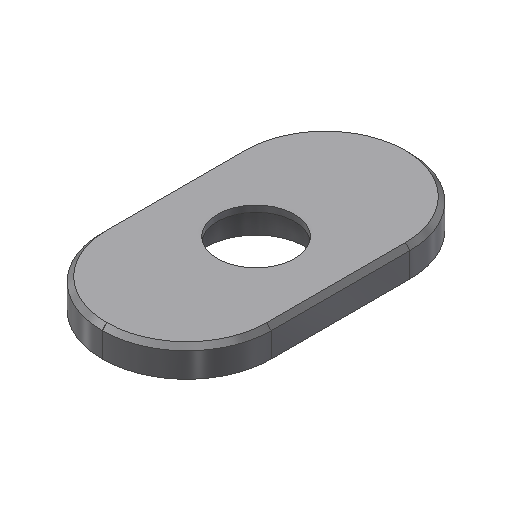
# Autodesk Inventor part: PRT - 9035 - CAMTARNDF - V04
Saved by Autodesk Inventor 2025.5 (Build 295498000, 498)
## iProperties
Created: 2026-11-05
Part Number: PRT - 9035 - CAMTARNDF - V04
Material: Generisch
Description: ND cap for the bare chip: filter D12.7 tilted by a pad, same seat and magnets. Print on the front.
Document SubType Name: Modeling
Designer: benir
Density: 1 g/cm^3
Appearance: Smooth - Light Gray
Author: benir
Autodesk Inventor part; units mm, degrees
ref_plane "y=cap_back_y" through (0, 12.3, 0) normal (0, 1, 0) x (-1, 0, 0)
sketch "cap sketch" plane through (0, 12.3, 0) normal (0, 1, 0) x (-1, 0, 0)
  line L0 (11, -20) -> (-11, -20)
  line L1 (-11, -20) -> (-11, 20)
  line L2 (-11, 20) -> (11, 20)
  line L3 (11, 20) -> (11, -20)
  line L4 (0, -28) -> (0, 28) projected
  line L5 (15.4, 0) -> (-15.4, 0) projected
  dimension "d3" = 22
  dimension "d4" = 40
  constraints: 8 end point, 2 parallel, 1 horizontal, 1 perpendicular, 2 other
  measures "d3" distance of L0.start L0.end
  measures "d4" distance of L2.end L0.start
extrude "cap" add sketch "cap sketch" along normal blind 3.8
fillet "round ends" radius 10.98 4 edges at (11, 14.2, -20) (11, 14.2, 20) (-11, 14.2, 20) (-11, 14.2, -20)
sketch "ring sketch" plane through (0, 12.3, 0) normal (0, 1, 0) x (-1, 0, 0)
  circle A0 centre (0, 0) radius 10.6
  dimension "d8" = 21.2
  constraints: 1 centre point
  measures "d8" diameter of A0
extrude "centring ring" add sketch "ring sketch" against normal blind 0.6 draft -45
ref_plane "y=ring_tip_y - 1 mm" through (0, 10.7, 0) normal (0, 1, 0) x (-1, 0, 0)
sketch "filter pocket sketch" plane through (0, 10.7, 0) normal (0, 1, 0) x (-1, 0, 0)
  circle A0 centre (0, 0) radius 6.45
  dimension "d12" = 12.9
  constraints: 1 centre point
  measures "d12" diameter of A0
extrude "filter pocket" cut sketch "filter pocket sketch" along normal blind 4.6
ref_plane "y=screen_out_y + 1 mm" through (0, 17.1, 0) normal (0, 1, 0) x (-1, 0, 0)
sketch "window sketch" plane through (0, 17.1, 0) normal (0, 1, 0) x (-1, 0, 0)
  circle A0 centre (0, 0) radius 5
  dimension "d16" = 10
  constraints: 1 centre point
  measures "d16" diameter of A0
extrude "window" cut sketch "window sketch" against normal blind 2.8
sketch "cap magnet sketch" plane through (0, 12.3, 0) normal (0, 1, 0) x (-1, 0, 0)
  circle A0 centre (0, 15.5) radius 4.1
  line L0 (0, -28) -> (0, 28) projected
  circle A1 centre (0, -15.5) radius 4.1
  point P0 (0, 0)
  dimension "d19" = 15.5
  dimension "d20" = 8.2
  dimension "d21" = 15.5
  dimension "d22" = 8.2
  constraints: 2 centre point, 2 point on line
  measures "d19" distance of point (0, 0) A0.centre
  measures "d20" diameter of A0
  measures "d21" distance of point (0, 0) A1.centre
  measures "d22" diameter of A1
extrude "magnet pockets" cut sketch "cap magnet sketch" along normal blind 3.4
chamfer "front edge" distance 0.6 angle 45 8 edges at (-7.784, 16.1, -16.784) (0, 16.1, -20) (-11, 16.1, 0) (-7.784, 16.1, 16.784) (0, 16.1, 20) (7.784, 16.1, 16.784) (11, 16.1, 0) (7.784, 16.1, -16.784)
ref_plane "y=screen_out_y - nd_wall" through (0, 15.3, 0) normal (0, 1, 0) x (-1, 0, 0)
sketch "pad sketch" plane through (0, 15.3, 0) normal (0, 1, 0) x (-1, 0, 0)
  line L0 (-5.2, -3) -> (-7.35, -3)
  line L1 (-7.35, -3) -> (-7.35, 3)
  line L2 (-7.35, 3) -> (-5.2, 3)
  line L3 (-5.2, 3) -> (-5.2, -3)
  line L4 (15.4, 0) -> (-15.4, 0) projected
  point P0 (0, 0)
  dimension "d29" = 6
  dimension "d30" = 5.2
  dimension "d31" = 7.35
  constraints: 8 end point, 2 parallel, 1 horizontal, 1 perpendicular, 1 other
  measures "d29" distance of L2.end L0.start
  measures "d30" horizontal distance of point (0, 0) L2.end
  measures "d31" horizontal distance of point (0, 0) L0.end
extrude "pad: tilts the filter" add sketch "pad sketch" against normal blind 0.7
equation "\"d3\" = 2 * cap_w"
equation "\"d4\" = 2 * cap_h"
equation "\"d5\" = cap_t"
equation "\"d8\" = ring_d0"
equation "\"d9\" = ring_h"
equation "\"d10\" = -cone_ang"
equation "\"d12\" = nd_d + nd_clr"
equation "\"d16\" = nd_win_d"
equation "\"d19\" = mag_z"
equation "\"d20\" = mag_pocket_d"
equation "\"d21\" = mag_z"
equation "\"d22\" = mag_pocket_d"
equation "\"d23\" = mag_pocket_h"
equation "\"d25\" = cap_edge"
equation "\"d26\" = cap_edge"
equation "\"d32\" = nd_pad"
equation "\"front_y\" = 12.2"
equation "\"cap_gap\" = 0.1"
equation "\"cap_back_y\" = front_y + cap_gap"
equation "\"d2\" = cap_back_y"
equation "\"cap_w\" = 11"
equation "\"sensor_y\" = -4.5"
equation "\"screen_in_y\" = sensor_y + screen_d"
equation "\"scr_t\" = 0.6"
equation "\"screen_out_y\" = screen_in_y + scr_t"
equation "\"cap_t\" = screen_out_y - cap_back_y"
equation "\"seat_c\" = 0.5"
equation "\"seat_r\" = 0.5 * bore_d + seat_c"
equation "\"ring_r0\" = seat_r + cap_gap"
equation "\"ring_d0\" = 2 * ring_r0"
equation "\"ring_h\" = 0.6"
equation "\"cone_ang\" = 45deg"
equation "\"ring_tip_y\" = cap_back_y - ring_h"
equation "\"nd_d\" = 12.7"
equation "\"nd_clr\" = 0.2"
equation "\"nd_wall\" = 0.8"
equation "\"nd_win_d\" = 10"
equation "\"mag_z\" = 15.5"
equation "\"mag_d\" = 8"
equation "\"mag_fit\" = 0.2"
equation "\"mag_pocket_d\" = mag_d + mag_fit"
equation "\"mag_t\" = 3"
equation "\"mag_sink\" = 0.4"
equation "\"mag_pocket_h\" = mag_t + mag_sink"
equation "\"cap_edge\" = 0.6"
equation "\"d28\" = screen_out_y - nd_wall"
equation "\"nd_pad\" = 0.7"
equation "\"cap_h\" = 20"
equation "\"screen_d\" = 20"
equation "\"bore_d\" = 20"
body "Solid2"
